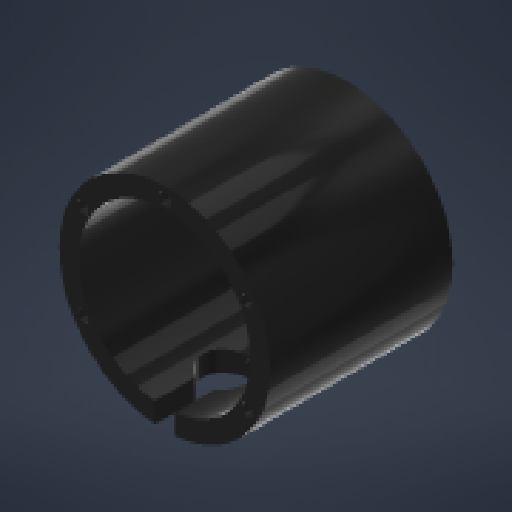
# Autodesk Inventor part: part
Saved by Autodesk Inventor 2027.1 (Build 311270010, 270A)
## iProperties
Created: 2026-10-16
Part Number: part
Material: Printed PLA Plastic
Document SubType Name: Modeling
Designer: youss
Density: 1.14 g/cm^3
Appearance: Smooth - Black
Author: youss
Autodesk Inventor part; units mm, degrees
sketch "Sketch1" plane through (0, 0, 0) normal (0, 0, 1) x (1, 0, 0)
  circle A0 centre (0, 0) radius 37
  circle A1 centre (0, -33) radius 2
  circle A2 centre (0, 0) radius 30
  line L0 (0, -33) -> (0, 0)
  circle A3 centre (28.5788, -16.5) radius 2
  circle A4 centre (28.5788, 16.5) radius 2
  circle A5 centre (0, 33) radius 2
  circle A6 centre (-28.5788, 16.5) radius 2
  circle A7 centre (-28.5788, -16.5) radius 2
  circle A8 centre (0, 0) radius 5
  circle A9 centre (0, 0) radius 11
  circle A10 centre (-8, 0) radius 1.6
  circle A11 centre (0, 8) radius 1.6
  circle A12 centre (8, 0) radius 1.6
  circle A13 centre (0, -8) radius 1.6
  circle A14 centre (0, 0) radius 2
  line L1 (0, 0) -> (0, 33)
  dimension "d16" = 60
  dimension "d17" = 74
  dimension "d18" = 4
  dimension "d22" = 360
  constraints: 15 centre point, 4 end point, 1 collinear, 1 concentric, 1 vertical, 16 other
  measures "d16" diameter of A2
  measures "d17" diameter of A0
  measures "d18" diameter of A1
extrude "Extrusion1" add sketch "Sketch1" along normal blind 4 contours A0 | A2 L0 A9 L1 | L1 A9 L0 A2 | L1 A11 A8 L0 A13 A9 | A9 L0 A13 A8 L1 A11 | L1 A14 L0 A8 | A8 L0 A14 L1
extrude "Extrusion2" add sketch "Sketch1" against normal blind 11.8 contours A0 | A3 | A4 | A5 | A6 | A7
chamfer "Chamfer1" distance 2 angle 45 4 edges at (-9.6, 0, 4) (-1.6, 8, 4) (-1.6, -8, 4) (6.4, 0, 4)
extrude "Extrusion3" add sketch "Sketch1" along normal blind 44 contours A0
ref_plane "Work Plane1" through (0, -40, 0) normal (0, 1, 0) x (-1, 0, 0)
sketch "Sketch6" plane through (0, 0, 4) normal (0, 0, 1) x (1, 0, 0)
  circle A0 centre (-16, -7) radius 2
  circle A1 centre (16, -7) radius 2
  circle A2 centre (-16, 7) radius 2
  circle A3 centre (16, 7) radius 2
  line L0 (16, -7) -> (-16, -7)
  line L1 (-16, -7) -> (-16, 7)
  line L2 (-16, 7) -> (16, 7)
  line L3 (16, 7) -> (16, -7)
  point P0 (0, 0)
  point P1 (0, 0)
  dimension "d24" = 4
  dimension "d25" = 32
  dimension "d26" = 14
  constraints: 8 end point, 4 centre point, 3 equal radius, 2 coincident, 2 parallel, 1 horizontal, 1 perpendicular
  measures "d24" diameter of A1
  measures "d25" distance of L0.start L0.end
  measures "d26" distance of L2.end L0.start
extrude "Extrusion7" cut sketch "Sketch6" against normal through all contours L0 L1 A0 | A0 L1 L0 | L0 L3 A1 | A1 L3 L0 | L1 L2 A2 | A2 L2 L1 | L3 L2 A3 | A3 L2 L3
move faces "Move1" translate (0, 0, 8) faces at (34.3574, -2.7444, 44)
ref_plane "Work Plane2" through (0, 37, 0) normal (0, 1, 0) x (-1, 0, 0)
sketch "Sketch7" plane through (0, 37, 0) normal (0, 1, 0) x (-1, 0, 0)
  circle A0 centre (0, 30) radius 11.5571
  line L0 (37, 52) -> (-37, 52) projected
  point P0 (0, 0)
  dimension "d32" = 22
  constraints: 1 centre point
  measures "d32" distance from line of L0 A0.centre
ref_plane "Work Plane5" through (0, -37, 0) normal (0, 1, 0) x (-1, 0, 0)
sketch "Sketch8" plane through (0, -37, 0) normal (0, 1, 0) x (-1, 0, 0)
  circle A0 centre (0, 30) radius 8.5
  line L0 (37, 52) -> (-37, 52) projected
  line L1 (0, 0) -> (0, 52)
  dimension "d33" = 22
  dimension "d34" = 17
  constraints: 2 end point, 1 centre point, 1 midpoint, 1 point on line
  measures "d33" distance from line of L0 A0.centre
  measures "d34" diameter of A0
extrude "Extrusion8" cut sketch "Sketch8" along normal blind 24.25
sketch "Sketch9" plane through (0, 0, 52) normal (0, 0, 1) x (1, 0, 0)
  line L0 (-3.5, -37) -> (3.5, -37)
  line L1 (3.5, -37) -> (3.5, -29.7951)
  line L2 (3.5, -29.7951) -> (-3.5, -29.7951)
  line L3 (-3.5, -29.7951) -> (-3.5, -37)
  circle A0 centre (0, 0) radius 37 projected
  circle A1 centre (0, 0) radius 30 projected
  point P0 (-3.5, -33.3976)
  point P1 (3.5, -33.3976)
  point P2 (-3.5, -36.8341)
  point P3 (3.5, -36.8341)
  dimension "d37" = 7
  constraints: 8 end point, 2 midpoint, 2 parallel, 2 point on circle, 1 horizontal, 1 perpendicular, 1 tangent
  measures "d37" distance of point (-3.5, -33.398) point (3.5, -33.398)
extrude "Extrusion9" cut sketch "Sketch9" against normal blind 15.75 contours A0 L3 A1 L1 picked at (0, -32.3181)
body "Solid1"
